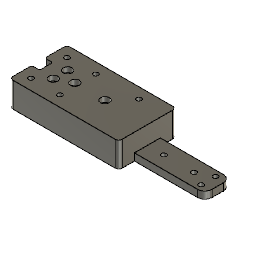
astra-ai-bracket (Autodesk Fusion 360 design; units mm, degrees)
part number: 2026-04-21-12-29-56-811
Autodesk Fusion 360 part; units mm, degrees
sketch "Sketch1" plane through (0, 0, 0) normal (0, 0, 1) x (1, 0, 0)
  line L0 (5, 0) -> (147.0004, 0)
  line L1 (0.0004, 80) -> (147.0004, 80)
  line L2 (152.0004, 75) -> (152.0004, 5)
  circle A0 centre (15.0237, 65) radius 9
  circle A1 centre (55.0237, 65) radius 9
  circle A2 centre (55.013, 15) radius 9
  circle A3 centre (15.013, 15) radius 9
  circle A4 centre (115.3487, 65) radius 9
  line L3 (0.0004, 80) -> (5, 80)
  line L4 (0, 5) -> (0, 75)
  circle A5 centre (15.0237, 65) radius 3.425
  circle A6 centre (55.0237, 65) radius 3.425
  circle A7 centre (55.013, 15) radius 3.425
  circle A8 centre (15.013, 15) radius 3.425
  circle A9 centre (115.3487, 65) radius 3.425
  line L5 (22, 58) -> (240, 58)
  line L6 (250, 48) -> (250, 32)
  line L7 (240, 22) -> (22, 22)
  line L8 (22, 22) -> (22, 58)
  arc A10 (147.0004, 0) -> (152.0004, 5) centre (147.0004, 5) ccw
  arc A11 (152.0004, 75) -> (147.0004, 80) centre (147.0004, 75) ccw
  arc A12 (5, 80) -> (0, 75) centre (5, 75) ccw
  arc A13 (0, 5) -> (5, 0) centre (5, 5) ccw
  arc A14 (250, 48) -> (240, 58) centre (240, 48) ccw
  arc A15 (240, 22) -> (250, 32) centre (240, 32) ccw
  point P0 (152.0004, 80)
  point P1 (152.0004, 0)
  point P2 (250, 58)
  point P3 (250, 22)
  dimension "d4" = 152
  dimension "d5" = 80
  dimension "d7" = 18
  dimension "d8" = 18
  dimension "d9" = 18
  dimension "d10" = 18
  dimension "d11" = 15
  dimension "d16" = 40
  dimension "d17" = 15
  dimension "d18" = 40
  dimension "d19" = 18
  dimension "d21" = 65
  dimension "d22" = 50
  dimension "d23" = 50
  dimension "d279" = 6.85
  dimension "d280" = 6.85
  dimension "d281" = 6.85
  dimension "d282" = 6.85
  dimension "d283" = 6.85
  dimension "d456" = 36
  dimension "d457" = 22
  dimension "d458" = 228
  dimension "d484" = 5
  dimension "d485" = 5
  dimension "d486" = 5
  dimension "d487" = 5
  dimension "d495" = 60.325
  dimension "d513" = 10
  dimension "d514" = 10
  constraint horizontal L0
  constraint horizontal L1
  constraint coincident L0 P1
  constraint perpendicular L0 L2
  constraint concentric A0 A5
  constraint concentric A1 A6
  constraint concentric A2 A7
  constraint concentric A3 A8
  constraint concentric A4 A9
  constraint horizontal L5
  constraint vertical L6
  constraint horizontal L7
  constraint vertical L8
  constraint coincident P1 L2
  constraint tangent L2 A10
  constraint tangent L0 A10
  constraint coincident P0 L1
  constraint coincident P0 L2
  constraint tangent L1 A11
  constraint tangent L2 A11
  constraint tangent L3 A12
  constraint tangent L4 A12
  constraint tangent L0 A13
  constraint tangent L4 A13
  constraint coincident P2 L5
  constraint coincident P2 L6
  constraint tangent L5 A14
  constraint tangent L6 A14
  constraint coincident P3 L6
  constraint coincident P3 L7
  constraint tangent L6 A15
  constraint tangent L7 A15
  measures "d4" distance of L1.start P0
  measures "d5" distance of P0 P1
  measures "d7" diameter of A0
  measures "d8" diameter of A1
  measures "d9" diameter of A2
  measures "d10" diameter of A3
  measures "d11" distance of L0 A3.centre
  measures "d16" distance of A0.centre A1.centre
  measures "d17" distance of L0 A2.centre
  measures "d18" distance of A2.centre A3.centre
  measures "d19" diameter of A4
  measures "d21" distance of L0 A4.centre
  measures "d22" distance of A0.centre A3.centre
  measures "d23" distance of A1.centre A2.centre
  measures "d279" diameter of A5
  measures "d280" diameter of A6
  measures "d281" diameter of A7
  measures "d282" diameter of A8
  measures "d283" diameter of A9
  measures "d456" distance of P2 P3
  measures "d457" vertical distance of P0 P2
  measures "d458" distance of P3 L7.end
  measures "d484" radius of A10
  measures "d485" radius of A11
  measures "d486" radius of A12
  measures "d487" radius of A13
  measures "d495" distance of A1.centre A4.centre
  measures "d513" radius of A14
  measures "d514" radius of A15
extrude "Extrude3" add sketch "Sketch1" along normal blind 35 contours L0 L1 L2 A1 A2 A4 L4 L5 L7 L8 A10 A11 A12 A13 | L2 A1 A2 A4 L5 L7 L8 | A2 L7 | A2 L7 | A4 L5 | A4 L5 | A1 L5 | A1 L5 | A0 | A3
sketch "Sketch20" plane through (0, 0, 0) normal (-1, 0, 0) x (0, -1, 0)
  line L0 (-75, 0) -> (-5, 0)
  line L1 (-5, 35) -> (-75, 35)
  line L2 (-5, 0) -> (-5, 35)
  line L3 (-75, 35) -> (-75, 0)
  line L4 (-31, 0) -> (-49, 0)
  line L5 (-49, 0) -> (-49, 35)
  line L6 (-49, 35) -> (-31, 35)
  line L7 (-31, 35) -> (-31, 0)
  point P0 (-75, 0)
  dimension "d489" = 18
  dimension "d490" = 26
  constraint horizontal L4
  constraint vertical L5
  constraint horizontal L6
  constraint vertical L7
  constraint coincident L1 L5.end
  constraint coincident L0 L4.start
  measures "d489" distance of L5.end L6.end
  measures "d490" distance of L4.end P0
extrude "Extrude58" cut sketch "Sketch20" along normal blind -11 and the other way blind -2 contours L0 L1 L4 L5 L6 L7
sketch "Sketch21" plane through (0, 0, 35) normal (0, 0, 1) x (-1, 0, 0)
  circle A0 centre (-15.013, -15) radius 3.425
  circle A1 centre (-55.0237, -65) radius 3.425
  circle A2 centre (-55.013, -15) radius 3.425
  circle A3 centre (-15.0237, -65) radius 3.425
  line L0 (0, -31) -> (0, -5)
  line L1 (-5, 0) -> (-147.0004, 0)
  line L2 (-152.0004, -5) -> (-152.0004, -75)
  line L3 (-147.0004, -80) -> (-5, -80)
  circle A4 centre (-31, -50) radius 3.425
  circle A5 centre (-31, -50) radius 6.125
  circle A6 centre (-31, -30) radius 3.425
  circle A7 centre (-31, -30) radius 6.125
  circle A8 centre (-51, -40) radius 3.425
  circle A9 centre (-51, -40) radius 6.125
  circle A10 centre (-93, -40) radius 3.425
  circle A11 centre (-93, -40) radius 6.125
  circle A12 centre (-115.3487, -65) radius 3.425
  arc A13 (-5, -80) -> (0, -75) centre (-5, -75) ccw
  arc A14 (0, -5) -> (-5, 0) centre (-5, -5) ccw
  arc A15 (-147.0004, 0) -> (-152.0004, -5) centre (-147.0004, -5) ccw
  arc A16 (-152.0004, -75) -> (-147.0004, -80) centre (-147.0004, -75) ccw
  line L4 (-11, -31) -> (0, -31)
  line L5 (0, -75) -> (0, -49)
  line L6 (0, -49) -> (-11, -49)
  line L7 (-11, -49) -> (-11, -31)
  circle A17 centre (-237, -50) radius 3.425
  circle A18 centre (-237, -50) radius 6.125
  circle A19 centre (-237, -30) radius 3.425
  circle A20 centre (-237, -30) radius 6.125
  circle A21 centre (-217, -40) radius 3.425
  circle A22 centre (-217, -40) radius 6.125
  circle A23 centre (-175, -40) radius 3.425
  circle A24 centre (-175, -40) radius 6.125
  point P0 (-250, -22)
  dimension "d464" = 6.85
  dimension "d465" = 12.25
  dimension "d466" = 6.85
  dimension "d467" = 12.25
  dimension "d470" = 20
  dimension "d472" = 6.85
  dimension "d473" = 12.25
  dimension "d474" = 20
  dimension "d475" = 10
  dimension "d476" = 6.85
  dimension "d477" = 12.25
  dimension "d478" = 42
  dimension "d479" = 10
  dimension "d488" = 157
  dimension "d496" = 6.85
  dimension "d497" = 12.25
  dimension "d498" = 206
  dimension "d499" = 6.85
  dimension "d500" = 12.25
  dimension "d501" = 206
  dimension "d502" = 20
  dimension "d503" = 6.85
  dimension "d504" = 12.25
  dimension "d505" = 20
  dimension "d506" = 6.85
  dimension "d507" = 12.25
  dimension "d508" = 42
  constraint concentric A4 A5
  constraint concentric A6 A7
  constraint concentric A8 A9
  constraint concentric A10 A11
  constraint concentric A17 A18
  constraint concentric A19 A20
  constraint concentric A21 A22
  constraint concentric A23 A24
  measures "d464" diameter of A4
  measures "d465" diameter of A5
  measures "d466" diameter of A6
  measures "d467" diameter of A7
  measures "d470" distance of A4.centre A6.centre
  measures "d472" diameter of A8
  measures "d473" diameter of A9
  measures "d474" horizontal distance of A4.centre A8.centre
  measures "d475" vertical distance of A4.centre A8.centre
  measures "d476" diameter of A10
  measures "d477" diameter of A11
  measures "d478" distance of A8.centre A10.centre
  measures "d479" vertical distance of A4.centre A10.centre
  measures "d488" horizontal distance of A10.centre P0
  measures "d496" diameter of A17
  measures "d497" diameter of A18
  measures "d498" distance of A4.centre A17.centre
  measures "d499" diameter of A19
  measures "d500" diameter of A20
  measures "d501" distance of A6.centre A19.centre
  measures "d502" distance of A17.centre A19.centre
  measures "d503" diameter of A21
  measures "d504" diameter of A22
  measures "d505" horizontal distance of A17.centre A21.centre
  measures "d506" diameter of A23
  measures "d507" diameter of A24
  measures "d508" distance of A21.centre A23.centre
extrude "Extrude63" add sketch "Sketch1" along normal blind 10 contours L2 L5 L6 L7 A14 A15
extrude "Extrude61" cut sketch "Sketch21" against normal blind 35 contours A4 | A6 | A8 | A10
extrude "Extrude62" cut sketch "Sketch21" against normal blind 7 contours A5 | A7 | A9 | A11
fillet "Fillet1" radius 3 2 edges at (0, 31, 17.5) (0, 49, 17.5)
fillet "Fillet2" radius 2 2 edges at (11, 31, 17.5) (11, 49, 17.5)
extrude "Extrude64" cut sketch "Sketch21" against normal blind 35 contours A17 | A19 | A21 | A23
named bodies: "astra-ai-bracket"
